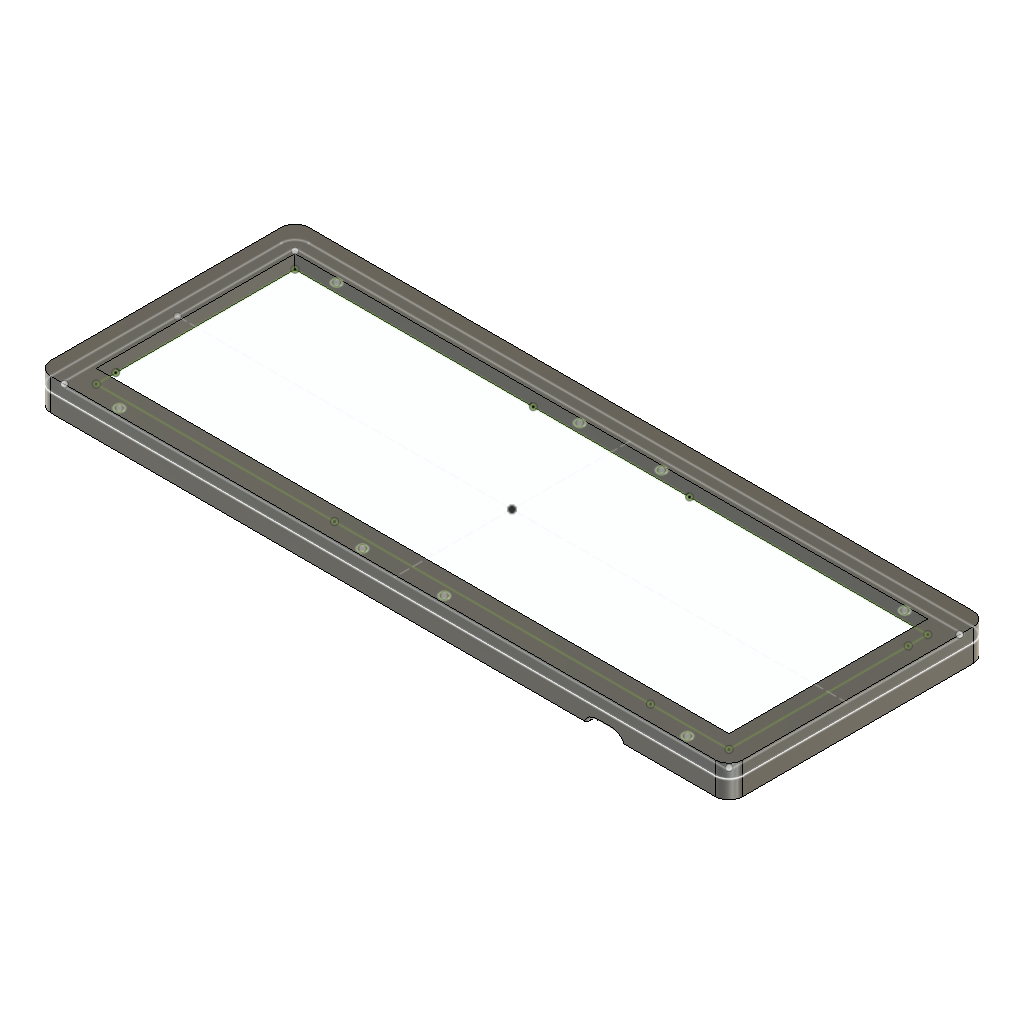
caseTop (Autodesk Fusion 360 design; units mm, degrees)
Autodesk Fusion 360 part; units mm, degrees
sketch "Sketch1" plane through (0, 0, 0) normal (0, 0, 1) x (1, 0, 0)
  circle A0 centre (32.6975, -12.4391) radius 1.7 construction
  circle A1 centre (-74.3025, -12.4391) radius 1.7 construction
  circle A2 centre (-110.3025, -12.4391) radius 1.7 construction
  circle A3 centre (-217.3025, -12.4391) radius 1.7 construction
  circle A4 centre (-217.3025, 83.2091) radius 1.7 construction
  circle A5 centre (-110.3025, 83.2091) radius 1.7 construction
  circle A6 centre (-74.3025, 83.2091) radius 1.7 construction
  circle A7 centre (32.6975, 83.2091) radius 1.7 construction
  line L0 (46.935, 70.535) -> (46.935, -8.35)
  line L1 (46.935, -8.35) -> (12.3912, -8.35)
  line L2 (12.3912, -8.35) -> (-126.6963, -8.35)
  line L3 (-126.6963, -8.35) -> (-231.54, -8.35)
  line L4 (-231.54, -8.35) -> (-231.54, 0.235)
  line L5 (-231.54, 0.235) -> (-231.54, 79.12)
  line L6 (-231.54, 79.12) -> (-126.6962, 79.12)
  line L7 (-126.6962, 79.12) -> (-57.9087, 79.12)
  line L8 (-57.9087, 79.12) -> (46.935, 79.12)
  line L9 (46.935, 79.12) -> (46.935, 70.535)
  line L10 (-239.56, 86.12) -> (-239.56, -15.35)
  arc A8 (-239.56, -15.35) -> (-238.54, -16.37) centre (-238.54, -15.35) ccw
  line L11 (-238.54, -16.37) -> (53.935, -16.37)
  arc A9 (53.935, -16.37) -> (54.955, -15.35) centre (53.935, -15.35) ccw
  line L12 (54.955, -15.35) -> (54.955, 86.12)
  arc A10 (54.955, 86.12) -> (53.935, 87.14) centre (53.935, 86.12) ccw
  line L13 (53.935, 87.14) -> (-238.54, 87.14)
  arc A11 (-238.54, 87.14) -> (-239.56, 86.12) centre (-238.54, 86.12) ccw
  circle A12 centre (-217.3025, -12.4391) radius 1.95
  circle A13 centre (-110.3025, -12.4391) radius 1.95
  line L14 (-92.3025, 87.14) -> (-92.3025, -16.37) construction
  circle A14 centre (-74.3025, -12.4391) radius 1.95
  circle A15 centre (32.6975, -12.4391) radius 1.95
  line L15 (-239.56, 35.385) -> (54.955, 35.385) construction
  circle A16 centre (-217.3025, 83.2091) radius 1.95
  circle A17 centre (-110.3025, 83.2091) radius 1.95
  circle A18 centre (-74.3025, 83.2091) radius 1.95
  circle A19 centre (32.6975, 83.2091) radius 1.95
  line L16 (-238.54, -21.37) -> (53.935, -21.37)
  arc A20 (53.935, -21.37) -> (59.955, -15.35) centre (53.935, -15.35) ccw
  line L17 (59.955, -15.35) -> (59.955, 86.12)
  arc A21 (59.955, 86.12) -> (53.935, 92.14) centre (53.935, 86.12) ccw
  line L18 (53.935, 92.14) -> (-238.54, 92.14)
  arc A22 (-238.54, 92.14) -> (-244.56, 86.12) centre (-238.54, 86.12) ccw
  line L19 (-244.56, 86.12) -> (-244.56, -15.35)
  arc A23 (-244.56, -15.35) -> (-238.54, -21.37) centre (-238.54, -15.35) ccw
  point P0 (-92.3025, 35.385)
  dimension "d2" = 8.02
  dimension "d3" = 8.02
  dimension "d4" = 1.02
  dimension "d5" = 1.02
  dimension "d6" = 292.475
  dimension "d7" = 1.02
  dimension "d8" = 101.47
  dimension "d9" = 1.02
  dimension "d10" = 8.02
  dimension "d11" = 8.02
  dimension "d12" = 3.9
  dimension "d13" = 3.9
  dimension "d14" = 4.0891
  dimension "d15" = 5
  constraint tangent L11 A9
  constraint tangent A9 L12
  constraint tangent A8 L11
  constraint tangent L10 A11
  constraint tangent L13 A11
  constraint tangent A10 L13
  constraint concentric A3 A12
  constraint concentric A2 A13
  constraint midpoint L13 L14.start
  constraint midpoint L11 L14.end
  constraint symmetric A12 L14 A15
  constraint symmetric A13 L14 A14
  constraint midpoint L15 P0
  constraint coincident L14 P0
  constraint coincident L12 L15.end
  constraint perpendicular L12 L15
  constraint symmetric A12 L15 A16
  constraint symmetric A13 L15 A17
  constraint symmetric A14 L15 A18
  constraint symmetric A15 L15 A19
  measures "d2" distance of L6 L13
  measures "d3" distance of L5 L10
  measures "d4" radius of A11
  measures "d5" radius of A8
  measures "d6" distance of A8.end L11.end
  measures "d7" radius of A9
  measures "d8" distance of A9.end L12.end
  measures "d9" radius of A10
  measures "d10" distance of L3 L11
  measures "d11" distance of L0 L12
  measures "d12" diameter of A12
  measures "d13" diameter of A13
  measures "d14" distance of L6 A4.centre
extrude "Extrude1" add sketch "Sketch1" along normal blind 6 contours L10 A8 L11 A9 L12 A10 L13 A11 | A12 | A13 | A14 | A15 | A16 | A17 | A18 | A19 | L16 A20 L17 A21 L18 A22 L19 A23 makes body 1
extrude "Extrude2" add sketch "Sketch1" against normal blind 6 separate body contours L16 A20 L17 A21 L18 A22 L19 A23 makes body 2
combine "Combine1" operation add target body 1 tool bodies 2
extrude "Extrude3" add 1 faces at (-141.0483, 90.4733, -6) along direction (0, 0, -1) blind 2 on bodies 1 bodies 1
extrude "Extrude4" cut sketch "Sketch1" along normal blind 5 contours A12 | A13 | A14 | A15 | A16 | A17 | A18 | A19 bodies 1
sketch "Sketch2" plane through (0, -21.37, 0) normal (0, -1, 0) x (1, 0, 0)
  line L0 (53.935, -8) -> (53.935, 6)
  line L1 (53.935, 6) -> (-238.54, 6)
  line L2 (-238.54, 6) -> (-238.54, -8)
  line L3 (-238.54, -8) -> (53.935, -8)
  line L4 (1.8105, -6.34) -> (8.2905, -6.34)
  line L5 (-8.9475, 8.35) -> (-8.9475, 9.29)
  line L6 (-2.1695, -12.349) -> (-2.1695, -10.32)
  arc A0 (1.8105, -6.34) -> (-2.1695, -10.32) centre (1.8105, -10.32) ccw
  arc A1 (12.2705, -10.32) -> (8.2905, -6.34) centre (8.2905, -10.32) ccw
  line L7 (-2.1695, -12.349) -> (-2.1695, -22.349)
  line L8 (12.2705, -22.349) -> (-2.1695, -22.349)
  line L9 (12.2705, -10.32) -> (12.2705, -22.349)
  line L10 (-3.1695, -12.349) -> (-3.1695, -23.349)
  line L11 (13.2705, -23.349) -> (-3.1695, -23.349)
  line L12 (13.2705, -10.32) -> (13.2705, -23.349)
  arc A2 (13.2705, -10.32) -> (8.2905, -5.34) centre (8.2905, -10.32) ccw
  line L13 (1.8105, -5.34) -> (8.2905, -5.34)
  arc A3 (1.8105, -5.34) -> (-3.1695, -10.32) centre (1.8105, -10.32) ccw
  line L14 (-3.1695, -12.349) -> (-3.1695, -10.32)
  point P0 (5.0505, 0.43)
  point P1 (5.0505, -4.67)
  point P2 (5.0505, -4.67)
  point P3 (-92.3025, 0.43)
  dimension "d26" = 97.353
  dimension "d32" = 10
  dimension "d34" = -1
  constraint coincident P2 P1
  constraint perpendicular L3 L7
  constraint perpendicular L7 L8
  constraint coincident L8 L9.end
  constraint tangent A1 L9
  constraint perpendicular L8 L9
  measures "d26" distance of P0 P3
  measures "d32" distance of L6.start L7.end
extrude "Extrude5" cut sketch "Sketch2" against normal blind 29 contours L3 L6 A0 A1 L7 L8 L9 L10 L11 L12 A2 A3 L14 | L3 L4 A0 A1 A2 L13 A3 | L3 L6 A0 A1 L7 L8 L9 | L3 L4 A0 A1 bodies 1
fillet "Fillet1" radius 1 3 edges at (-0.7631, -21.37, -6.0566) (5.0505, -21.37, -5.34) (10.8641, -21.37, -6.0566) on bodies 1
